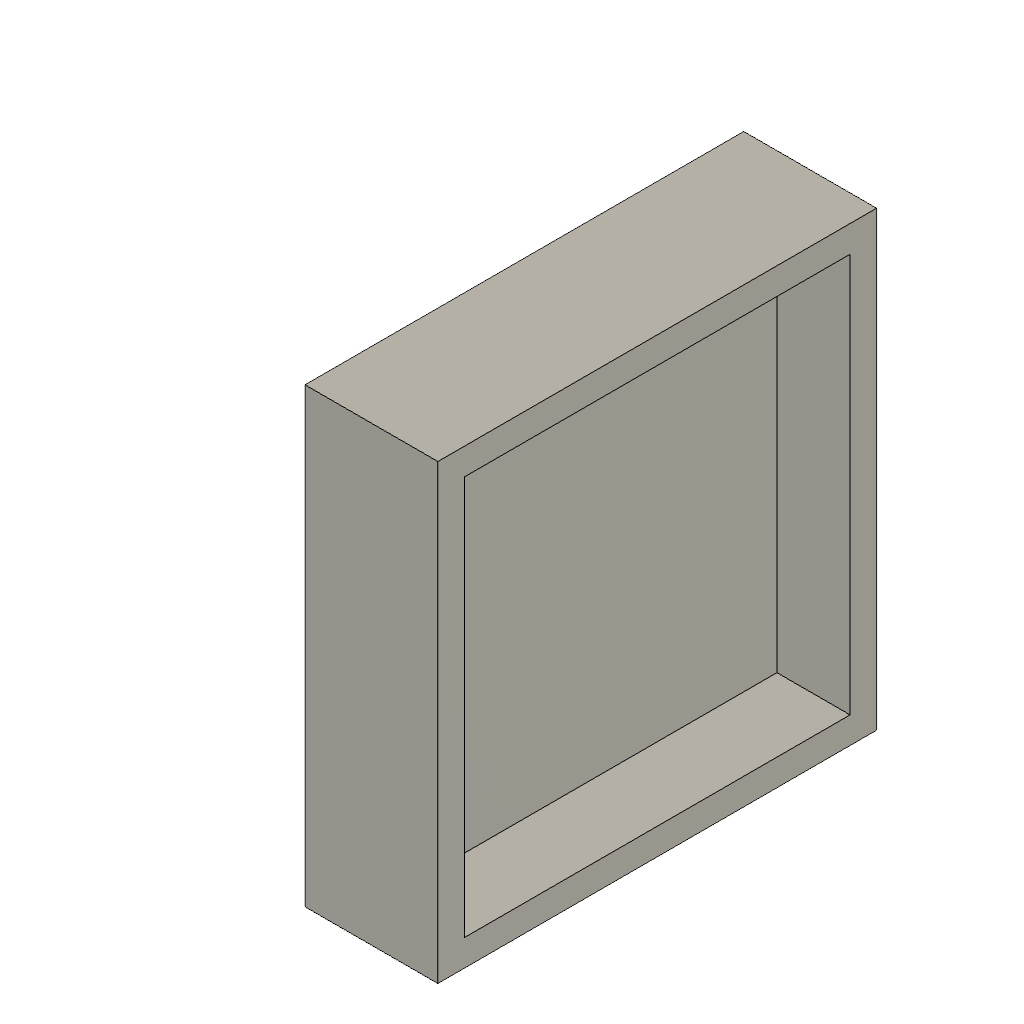
caja_pantalla (Autodesk Fusion 360 design; units mm, degrees)
Autodesk Fusion 360 part; units mm, degrees
sketch "Boceto2" plane through (0, 0, 0) normal (1, 0, 0) x (0, 0, -1)
  line L0 (16.5, 17) -> (-16.5, 17)
  line L1 (-16.5, 17) -> (-16.5, -17)
  line L2 (-16.5, -17) -> (16.5, -17)
  line L3 (16.5, -17) -> (16.5, 17)
  line L4 (16.5, 17) -> (-16.5, -17) construction
  line L5 (-16.5, 17) -> (16.5, -17) construction
  dimension "d1" = 33
  dimension "d2" = 34
  constraint horizontal L0
  constraint perpendicular L0 L1
  constraint parallel L0 L2
  constraint parallel L1 L3
  constraint coincident L4 origin
  constraint coincident L5 origin
  measures "d1" distance of L1.end L2.end
  measures "d2" distance of L0.end L1.end
extrude "Extruir1" add sketch "Boceto2" along normal blind 10
sketch "Boceto3" plane through (10, 0, 0) normal (1, 0, 0) x (0, 0, -1)
  line L0 (16.5, -17) -> (16.5, 17)
  line L1 (16.5, 17) -> (-16.5, 17)
  line L2 (-16.5, 17) -> (-16.5, -17)
  line L3 (-16.5, -17) -> (16.5, -17)
  line L4 (14.5, 15) -> (-14.5, 15)
  line L5 (-14.5, 15) -> (-14.5, -15)
  line L6 (-14.5, -15) -> (14.5, -15)
  line L7 (14.5, -15) -> (14.5, 15)
  line L8 (14.5, 15) -> (-14.5, -15) construction
  line L9 (-14.5, 15) -> (14.5, -15) construction
  dimension "d5" = 29
  dimension "d6" = 30
  constraint horizontal L4
  constraint perpendicular L4 L5
  constraint parallel L4 L6
  constraint parallel L5 L7
  constraint coincident L8 origin
  constraint coincident L9 origin
  measures "d5" distance of L5.end L6.end
  measures "d6" distance of L4.end L5.end
extrude "Extruir2" cut sketch "Boceto3" against normal blind 5.5 contours L4 L5 L6 L7
sketch "Boceto4" plane through (4.5, 0, 0) normal (1, 0, 0) x (0, 0, -1)
  line L0 (14.5, -15) -> (14.5, 15)
  line L1 (14.5, 15) -> (-14.5, 15)
  line L2 (-14.5, 15) -> (-14.5, -15)
  line L3 (-14.5, -15) -> (14.5, -15)
  line L4 (5.1, 13.25) -> (-4.9, 13.25)
  line L5 (-4.9, 13.25) -> (-4.9, 10.75)
  line L6 (-4.9, 10.75) -> (5.1, 10.75)
  line L7 (5.1, 10.75) -> (5.1, 13.25)
  line L8 (5.1, 13.25) -> (-4.9, 10.75) construction
  line L9 (-4.9, 13.25) -> (5.1, 10.75) construction
  line L10 (16.5, 17) -> (-16.5, 17)
  point P0 (0.1, 12)
  dimension "d9" = 10
  dimension "d10" = 2.5
  dimension "d11" = 5
  dimension "d26" = 0.1
  constraint horizontal L4
  constraint perpendicular L4 L5
  constraint parallel L4 L6
  constraint parallel L5 L7
  constraint coincident L8 P0
  constraint coincident L9 P0
  measures "d9" distance of L5.end L6.end
  measures "d10" distance of L4.end L5.end
  measures "d11" distance of P0 L10
  measures "d26" horizontal distance of origin P0
extrude "Extruir3" cut sketch "Boceto4" against normal blind 5 contours L4 L5 L6 L7
sketch "Boceto5" plane through (0, 0, 16.5) normal (0, 0, 1) x (1, 0, 0)
  line L0 (0, 17) -> (0, -17)
  line L1 (0, -17) -> (10, -17)
  line L2 (10, -17) -> (10, 17)
  line L3 (10, 17) -> (0, 17)
  line L4 (0, 9.3366) -> (-3.6138, -2.125)
  line L5 (0, -17) -> (-11.8505, -17)
  line L6 (-11.8505, -17) -> (-11.8505, -2.125)
  line L7 (-11.8505, -2.125) -> (-3.6138, -2.125)
  dimension "d14" = 17.5
  constraint coincident L0 L4.start
  constraint coincident L0.end L1.start
  constraint perpendicular L0 L5
  constraint perpendicular L5 L6
  constraint perpendicular L6 L7
  measures "d14" angle of L0 L4
extrude "Extruir4" add sketch "Boceto5" against normal blind 31 contours L0 L4 L5 L6 L7
sketch "Boceto6" plane through (0, 0, 16.5) normal (0, 0, 1) x (1, 0, 0)
  line L0 (0, 17) -> (0, 9.3366)
  line L1 (0, 9.3366) -> (-3.6138, -2.125)
  line L2 (-3.6138, -2.125) -> (-11.8505, -2.125)
  line L3 (-11.8505, -2.125) -> (-11.8505, -17)
  line L4 (-11.8505, -17) -> (10, -17)
  line L5 (10, -17) -> (10, 17)
  line L6 (10, 17) -> (0, 17)
  line L7 (0, 9.3366) -> (-3.6138, -2.125)
  line L8 (-11.8505, -2.125) -> (-11.8505, -17)
  line L9 (0, -17) -> (-11.8505, -17)
  line L10 (-11.8505, -2.125) -> (-11.8505, -17)
  line L11 (0, -17) -> (0, 9.3366)
  line L12 (-11.8505, -2.125) -> (-3.6138, -2.125)
  constraint coincident L0.end L1.start
  constraint coincident L1.end L2.start
  constraint coincident L2.end L3.start
  constraint coincident L3.end L4.start
  constraint coincident L4 L9.start
  constraint perpendicular L9 L11
extrude "Extruir5" cut sketch "Boceto6" against normal blind 20 contours L1 L2 L3 L4 L7 L8 L9 L10 L11 L12
fillet "Empalme1" radius 4 1 edges at (0, -3.8317, -3.5)
sketch "Boceto7" plane through (0, 0, -3.5) normal (0, 0, 1) x (1, 0, 0)
  line L0 (-4, -17) -> (-4, -2.125)
  line L1 (-4, -2.125) -> (-11.8505, -2.125)
  line L2 (-11.8505, -2.125) -> (-11.8505, -17)
  line L3 (-11.8505, -17) -> (-4, -17)
  circle A0 centre (-7.9252, -9.0625) radius 1.95
  dimension "d21" = 3.9
  measures "d21" diameter of A0
extrude "Extruir6" cut sketch "Boceto7" against normal blind 15 contours A0
fillet "Empalme2" radius 1 1 edges at (-9.7433, -8.3574, -3.5)
